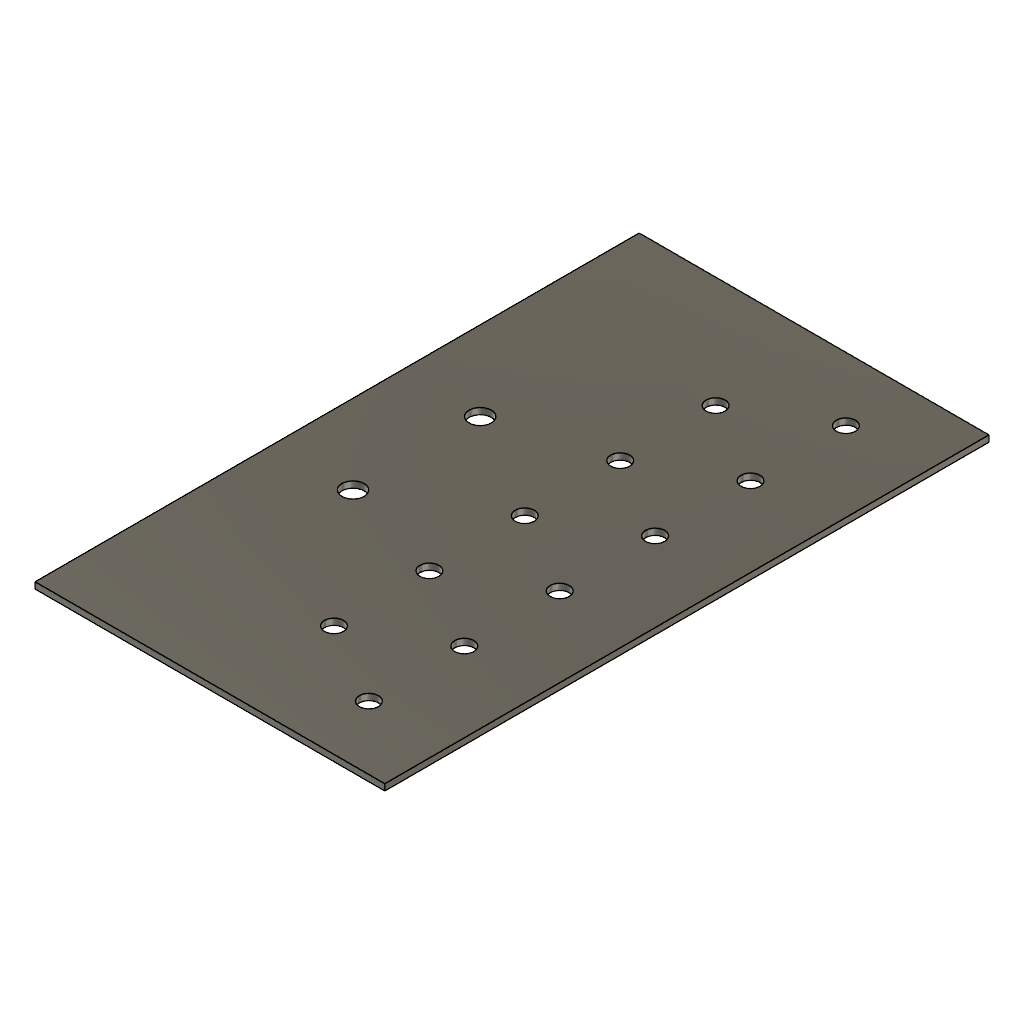
panel (Autodesk Fusion 360 design; units mm, degrees)
part number: 2026-09-27-12-58-00-016
Autodesk Fusion 360 part; units mm, degrees
sketch "Sketch2" plane through (0, 0, 0) normal (0, 0, 1) x (1, 0, 0)
  line L0 (0, 0) -> (-110, 0)
  line L1 (-110, 0) -> (-110, -190)
  line L2 (-110, -190) -> (0, -190)
  line L3 (0, -190) -> (0, 0)
  dimension "d9" = 110
  dimension "d10" = 190
  constraint horizontal L0
  constraint vertical L1
  constraint horizontal L2
  constraint vertical L3
  constraint coincident L0.start L3.end
  measures "d9" distance of L0.start L0.end
  measures "d10" distance of L0.start L2.end
extrude "Extrude2" add sketch "Sketch2" along normal blind 2
hole "Hole2" at (-25, -170, 2) direction (0, 0, -1) diameter 6 depth 2 tip angle 118
pattern_linear "R-Pattern1" count 6 spacing 30 along (0, 1, 0) of "Hole2"
sketch "Sketch3" plane through (0, 0, 2) normal (0, 0, 1) x (-1, 0, 0)
  line L0 (0, 190) -> (0, 0)
  line L1 (0, 0) -> (110, 0)
  line L2 (110, 0) -> (110, 190)
  line L3 (110, 190) -> (0, 190)
  circle A0 centre (25, 170) radius 3
  circle A1 centre (25, 140) radius 3
  circle A2 centre (25, 110) radius 3
  circle A3 centre (25, 80) radius 3
  circle A4 centre (25, 50) radius 3
  circle A5 centre (25, 20) radius 3
  point P0 (85, 75)
  point P1 (85, 115)
  dimension "d22" = 75
  dimension "d23" = 115
  dimension "d24" = 85
  dimension "d26" = 190
  dimension "d29" = 60
  dimension "d30" = 110
  dimension "d34" = 30
  measures "d22" distance of L1 P0
  measures "d23" distance of L1 P1
  measures "d24" distance of L0 P0
  measures "d26" distance of L0.start L0.end
  measures "d29" horizontal distance of A3.centre P0
  measures "d30" distance of L0.end L1.end
  measures "d34" distance of A2.centre A3.centre
hole "Hole3" at (-85, -115, 2) at (-85, -75, 2) direction (0, 0, -1) diameter 7 depth 2 tip angle 180
sketch "Sketch4" plane through (0, 0, 2) normal (0, 0, 1) x (-1, 0, 0)
  circle A0 centre (25, 20) radius 3
  circle A1 centre (25, 50) radius 3
  circle A2 centre (25, 80) radius 3
  circle A3 centre (25, 110) radius 3
  circle A4 centre (25, 140) radius 3
  circle A5 centre (25, 170) radius 3
  line L0 (0, 190) -> (0, 0)
  line L1 (0, 0) -> (110, 0)
  line L2 (110, 0) -> (110, 190)
  line L3 (110, 190) -> (0, 190)
  circle A6 centre (85, 75) radius 3.5
  circle A7 centre (85, 115) radius 3.5
sketch "Sketch5" plane through (0, 0, 2) normal (0, 0, 1) x (-1, 0, 0)
  line L0 (0, 0) -> (110, 0)
  point P0 (50.9808, 35)
  point P1 (25, 20)
  dimension "d38" = 30
  dimension "d39" = 35
  measures "d38" distance of P0 P1
  measures "d39" distance of P0 L0
hole "Hole4" at (-50.9808, -35, 2) direction (0, 0, -1) diameter 6 depth 3 tip angle 180
pattern_linear "R-Pattern2" count 5 spacing 30 along (0, -1, 0) of "Hole4"
sketch "Sketch11" plane through (0, 0, 2) normal (0, 0, 1) x (-1, 0, 0)
  circle A0 centre (50.9808, 35) radius 3
  circle A1 centre (25, 20) radius 3
  circle A2 centre (25, 50) radius 3
  circle A3 centre (25, 80) radius 3
  circle A4 centre (25, 110) radius 3
  circle A5 centre (25, 140) radius 3
  circle A6 centre (25, 170) radius 3
  line L0 (0, 190) -> (0, 0)
  line L1 (0, 0) -> (110, 0)
  line L2 (110, 0) -> (110, 190)
  line L3 (110, 190) -> (0, 190)
  circle A7 centre (85, 75) radius 3.5
  circle A8 centre (85, 115) radius 3.5
  circle A9 centre (50.9808, 65) radius 3
  circle A10 centre (50.9808, 95) radius 3
  circle A11 centre (50.9808, 125) radius 3
  circle A12 centre (50.9808, 155) radius 3
